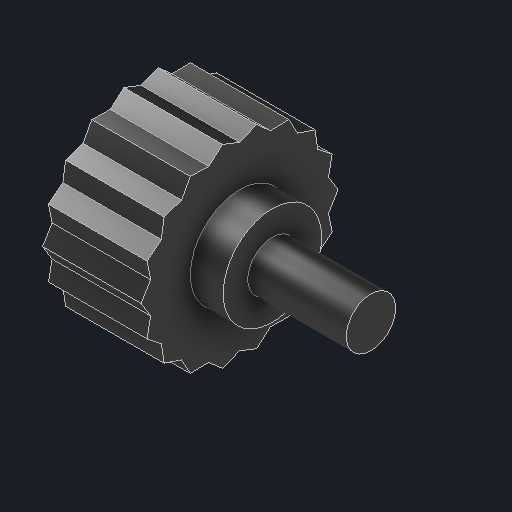
# Autodesk Inventor part: c8n_collimation_knob
Saved by Autodesk Inventor 2027.1 (Build 311270010, 270A)
## iProperties
Created: 2026-11-04
Part Number: c8n_collimation_knob
Material: Generic
Description: Primary collimation knob (x3)
Document SubType Name: Modeling
Designer: Claude (from photos)
Density: 1 g/cm^3
Appearance: Glossy - Black
Author: alexg
Autodesk Inventor part; units mm, degrees
ref_plane "XZ Plane" through (0, 0, 0) normal (0, 1, 0) x (-1, 0, 0)
ref_plane "Work Plane1" through (-16, 0, 0) normal (1, 0, 0) x (0, 1, 0)
sketch "Knurled knob sketch" plane through (-16, 0, 0) normal (1, 0, 0) x (0, 1, 0)
  line L0 (0, 12) -> (1.9101, 10.8329)
  line L1 (1.9101, 10.8329) -> (4.1042, 11.2763)
  line L2 (4.1042, 11.2763) -> (5.5, 9.5263)
  line L3 (5.5, 9.5263) -> (7.7135, 9.1925)
  line L4 (7.7135, 9.1925) -> (8.4265, 7.0707)
  line L5 (8.4265, 7.0707) -> (10.3923, 6)
  line L6 (10.3923, 6) -> (10.3366, 3.7622)
  line L7 (10.3366, 3.7622) -> (11.8177, 2.0838)
  line L8 (11.8177, 2.0838) -> (11, 0)
  line L9 (11, 0) -> (11.8177, -2.0838)
  line L10 (11.8177, -2.0838) -> (10.3366, -3.7622)
  line L11 (10.3366, -3.7622) -> (10.3923, -6)
  line L12 (10.3923, -6) -> (8.4265, -7.0707)
  line L13 (8.4265, -7.0707) -> (7.7135, -9.1925)
  line L14 (7.7135, -9.1925) -> (5.5, -9.5263)
  line L15 (5.5, -9.5263) -> (4.1042, -11.2763)
  line L16 (4.1042, -11.2763) -> (1.9101, -10.8329)
  line L17 (1.9101, -10.8329) -> (0, -12)
  line L18 (0, -12) -> (-1.9101, -10.8329)
  line L19 (-1.9101, -10.8329) -> (-4.1042, -11.2763)
  line L20 (-4.1042, -11.2763) -> (-5.5, -9.5263)
  line L21 (-5.5, -9.5263) -> (-7.7135, -9.1925)
  line L22 (-7.7135, -9.1925) -> (-8.4265, -7.0707)
  line L23 (-8.4265, -7.0707) -> (-10.3923, -6)
  line L24 (-10.3923, -6) -> (-10.3366, -3.7622)
  line L25 (-10.3366, -3.7622) -> (-11.8177, -2.0838)
  line L26 (-11.8177, -2.0838) -> (-11, 0)
  line L27 (-11, 0) -> (-11.8177, 2.0838)
  line L28 (-11.8177, 2.0838) -> (-10.3366, 3.7622)
  line L29 (-10.3366, 3.7622) -> (-10.3923, 6)
  line L30 (-10.3923, 6) -> (-8.4265, 7.0707)
  line L31 (-8.4265, 7.0707) -> (-7.7135, 9.1925)
  line L32 (-7.7135, 9.1925) -> (-5.5, 9.5263)
  line L33 (-5.5, 9.5263) -> (-4.1042, 11.2763)
  line L34 (-4.1042, 11.2763) -> (-1.9101, 10.8329)
  line L35 (-1.9101, 10.8329) -> (0, 12)
  constraints: 72 end point
extrude "Knurled knob" add sketch "Knurled knob sketch" along normal blind 12
ref_plane "Work Plane2" through (-4, 0, 0) normal (1, 0, 0) x (0, 1, 0)
sketch "Collar sketch" plane through (-4, 0, 0) normal (1, 0, 0) x (0, 1, 0)
  circle A0 centre (0, 0) radius 6
  constraints: 1 centre point
extrude "Collar" add sketch "Collar sketch" along normal blind 4
sketch "M6 collimation bolt sketch" plane through (0, 0, 0) normal (1, 0, 0) x (0, 1, 0)
  circle A0 centre (0, 0) radius 3
  constraints: 1 centre point
extrude "M6 collimation bolt" add sketch "M6 collimation bolt sketch" along normal blind 12
body "Solid1"
